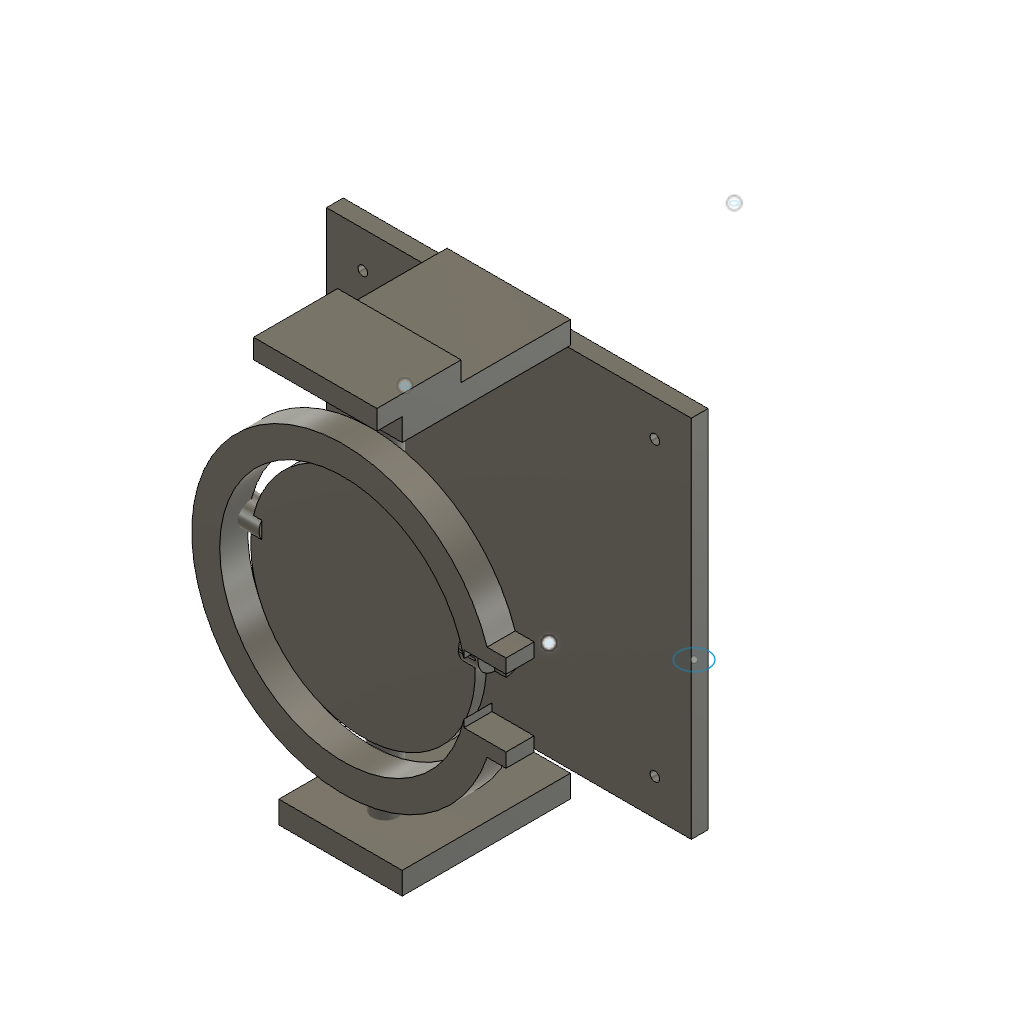
Gimbal2Axis (Autodesk Fusion 360 design; units mm, degrees)
part number: 2026-11-09-16-54-55-100
part number: 2026-11-09-16-54-55-282
part number: 2026-11-09-16-54-55-441
part number: 2026-11-09-16-54-55-850
Autodesk Fusion 360 part; units mm, degrees
ref_plane "工作平面1" through (0, 0, 0) normal (0, 0, 1) x (1, 0, 0) in component "Disc"
sketch "草图1" plane through (0, 0, 0) normal (0, 0, 1) x (1, 0, 0) in component "Disc"
  circle A0 centre (0, 0) radius 40
extrude "拉伸1" add sketch "草图1" along normal blind 4 makes body 1 in component "Disc"
ref_plane "工作平面2" through (36, 0, 0) normal (1, 0, 0) x (0, 1, 0) in component "Disc"
sketch "草图2" plane through (36, 0, 0) normal (1, 0, 0) x (0, 0, -1) in component "Disc"
  circle A0 centre (0, 6) radius 6
extrude "拉伸2" add sketch "草图2" along normal blind 11 bodies 1 in component "Disc"
ref_plane "工作平面3" through (-47, 0, 0) normal (1, 0, 0) x (0, 1, 0) in component "Disc"
sketch "草图3" plane through (-47, 0, 0) normal (1, 0, 0) x (0, 0, -1) in component "Disc"
  circle A0 centre (0, 6) radius 5
extrude "拉伸3" add sketch "草图3" along normal blind 11 bodies 1 in component "Disc"
ref_plane "工作平面4" through (34, 0, 0) normal (1, 0, 0) x (0, 1, 0) in component "Disc"
sketch "草图4" plane through (34, 0, 0) normal (1, 0, 0) x (0, 0, -1) in component "Disc"
  circle A0 centre (7, 6) radius 1.1
extrude "拉伸4" cut sketch "草图4" along normal blind 8 bodies 1 in component "Disc"
ref_plane "工作平面5" through (34, 0, 0) normal (1, 0, 0) x (0, 1, 0) in component "Disc"
sketch "草图5" plane through (34, 0, 0) normal (1, 0, 0) x (0, 0, -1) in component "Disc"
  circle A0 centre (-7, 6) radius 1.1
extrude "拉伸5" cut sketch "草图5" along normal blind 8 bodies 1 in component "Disc"
ref_plane "工作平面6" through (-48, 0, 0) normal (1, 0, 0) x (0, 1, 0) in component "Disc"
sketch "草图6" plane through (-48, 0, 0) normal (1, 0, 0) x (0, 0, -1) in component "Disc"
  circle A0 centre (0, 6) radius 1.55
extrude "拉伸6" cut sketch "草图6" along normal blind 13 bodies 1 in component "Disc"
ref_plane "工作平面7" through (0, 0, -0.1) normal (0, 0, 1) x (1, 0, 0) in component "Disc"
sketch "草图7" plane through (0, 0, -0.1) normal (0, 0, 1) x (1, 0, 0) in component "Disc"
  line L0 (-11, -8.5) -> (11, -8.5)
  line L1 (11, -8.5) -> (11, 8.5)
  line L2 (11, 8.5) -> (-11, 8.5)
  line L3 (-11, 8.5) -> (-11, -8.5)
extrude "拉伸7" cut sketch "草图7" along normal blind 1.6 bodies 1 in component "Disc"
ref_plane "工作平面1" through (0, 0, 0) normal (0, 0, 1) x (1, 0, 0) in component "Ring"
sketch "草图1 (2)" plane through (0, 0, 0) normal (0, 0, 1) x (1, 0, 0) in component "Ring"
  circle A0 centre (0, 0) radius 54
  circle A1 centre (0, 0) radius 44
extrude "拉伸1'" add sketch "草图1 (2)" along normal blind 10 separate body makes body 2 in component "Ring"
ref_plane "工作平面2" through (0, 0, 0) normal (0, 0, 1) x (1, 0, 0) in component "Ring"
sketch "草图2 (2)" plane through (0, 0, 0) normal (0, 0, 1) x (1, 0, 0) in component "Ring"
  line L0 (43, -12) -> (55, -12)
  line L1 (55, -12) -> (55, 12)
  line L2 (55, 12) -> (43, 12)
  line L3 (43, 12) -> (43, -12)
extrude "拉伸8" cut sketch "草图2 (2)" along normal blind 10 bodies 1 in component "Disc"
extrude "拉伸2'" cut sketch "草图2 (2)" along normal blind 10 bodies 2 in component "Ring"
ref_plane "工作平面3" through (0, 0, 0) normal (0, 0, 1) x (1, 0, 0) in component "Ring"
sketch "草图3 (2)" plane through (0, 0, 0) normal (0, 0, 1) x (1, 0, 0) in component "Ring"
  line L0 (50, 12) -> (58, 12)
  line L1 (58, 12) -> (58, 17)
  line L2 (58, 17) -> (50, 17)
  line L3 (50, 17) -> (50, 12)
extrude "拉伸3'" add sketch "草图3 (2)" along normal blind 10 bodies 2 in component "Ring"
ref_plane "工作平面4" through (0, 0, 0) normal (0, 0, 1) x (1, 0, 0) in component "Ring"
sketch "草图4 (2)" plane through (0, 0, 0) normal (0, 0, 1) x (1, 0, 0) in component "Ring"
  line L0 (50, -17) -> (58, -17)
  line L1 (58, -17) -> (58, -12)
  line L2 (58, -12) -> (50, -12)
  line L3 (50, -12) -> (50, -17)
extrude "拉伸4'" add sketch "草图4 (2)" along normal blind 10 bodies 2 in component "Ring"
ref_plane "工作平面5" through (49, 0, 0) normal (1, 0, 0) x (0, 1, 0) in component "Ring"
sketch "草图5 (2)" plane through (49, 0, 0) normal (1, 0, 0) x (0, 0, -1) in component "Ring"
  circle A0 centre (14.3, 5) radius 0.8
ref_plane "工作平面6" through (0, 42, 0) normal (0, 1, 0) x (0, 0, 1) in component "Ring"
sketch "草图6 (2)" plane through (0, 42, 0) normal (0, 1, 0) x (1, 0, 0) in component "Ring"
  circle A0 centre (0, 5) radius 5
extrude "拉伸5'" add sketch "草图6 (2)" along normal blind 32 bodies 2 in component "Ring"
ref_plane "工作平面7" through (0, -74, 0) normal (0, 1, 0) x (0, 0, 1) in component "Ring"
sketch "草图7 (2)" plane through (0, -74, 0) normal (0, 1, 0) x (1, 0, 0) in component "Ring"
  circle A0 centre (0, 5) radius 5
extrude "拉伸6'" add sketch "草图7 (2)" along normal blind 32 bodies 2 in component "Ring"
ref_plane "工作平面8" through (0, 68, 0) normal (0, 1, 0) x (0, 0, 1) in component "Ring"
sketch "草图8" plane through (0, 68, 0) normal (0, 1, 0) x (1, 0, 0) in component "Ring"
  circle A0 centre (7, 5) radius 1.1
ref_plane "工作平面9" through (0, -75, 0) normal (0, 1, 0) x (0, 0, 1) in component "Ring"
sketch "草图9" plane through (0, -75, 0) normal (0, 1, 0) x (1, 0, 0) in component "Ring"
  circle A0 centre (0, 5) radius 1.55
extrude "拉伸7'" cut sketch "草图9" along normal blind 33 bodies 2 in component "Ring"
ref_plane "工作平面10" through (-55, 0, 0) normal (1, 0, 0) x (0, 1, 0) in component "Ring"
sketch "草图10" plane through (-55, 0, 0) normal (1, 0, 0) x (0, 0, -1) in component "Ring"
  circle A0 centre (0, 5) radius 1.55
extrude "拉伸9" cut sketch "草图10" along normal blind 12 bodies 1 in component "Disc"
extrude "拉伸8'" cut sketch "草图10" along normal blind 12 bodies 2 in component "Ring"
ref_plane "工作平面1" through (0, 0, 0) normal (0, 0, 1) x (1, 0, 0) in component "Frame"
sketch "草图1 (3)" plane through (0, 0, 0) normal (0, 0, 1) x (1, 0, 0) in component "Frame"
  line L0 (-65, -65) -> (65, -65)
  line L1 (65, -65) -> (65, 65)
  line L2 (65, 65) -> (-65, 65)
  line L3 (-65, 65) -> (-65, -65)
extrude "拉伸1''" add sketch "草图1 (3)" along normal blind 6 separate body makes body 3 in component "Frame"
ref_plane "工作平面2" through (0, 0, 6) normal (0, 0, 1) x (1, 0, 0) in component "Frame"
sketch "草图2 (3)" plane through (0, 0, 6) normal (0, 0, 1) x (1, 0, 0) in component "Frame"
  line L0 (-22, 66) -> (22, 66)
  line L1 (22, 66) -> (22, 74)
  line L2 (22, 74) -> (-22, 74)
  line L3 (-22, 74) -> (-22, 66)
extrude "拉伸2''" add sketch "草图2 (3)" along normal blind 60 separate body makes body 4 in component "Frame"
ref_plane "工作平面3" through (0, 0, 6) normal (0, 0, 1) x (1, 0, 0) in component "Frame"
sketch "草图3 (3)" plane through (0, 0, 6) normal (0, 0, 1) x (1, 0, 0) in component "Frame"
  line L0 (-22, -74) -> (22, -74)
  line L1 (22, -74) -> (22, -66)
  line L2 (22, -66) -> (-22, -66)
  line L3 (-22, -66) -> (-22, -74)
extrude "拉伸3''" add sketch "草图3 (3)" along normal blind 60 separate body makes body 5 in component "Frame"
ref_plane "工作平面4" through (0, -75, 0) normal (0, 1, 0) x (0, 0, 1) in component "Frame"
sketch "草图4 (3)" plane through (0, -75, 0) normal (0, 1, 0) x (1, 0, 0) in component "Frame"
  circle A0 centre (0, 60) radius 5.25
ref_plane "工作平面5" through (0, 0, 45) normal (0, 0, 1) x (1, 0, 0) in component "Frame"
sketch "草图5 (3)" plane through (0, 0, 45) normal (0, 0, 1) x (1, 0, 0) in component "Frame"
  line L0 (-22, 74) -> (22, 74)
  line L1 (22, 74) -> (22, 81)
  line L2 (22, 81) -> (-22, 81)
  line L3 (-22, 81) -> (-22, 74)
extrude "拉伸4''" add sketch "草图5 (3)" along normal blind 30 bodies 4 in component "Frame"
ref_plane "工作平面6" through (0, 73, 0) normal (0, 1, 0) x (0, 0, 1) in component "Frame"
sketch "草图6 (3)" plane through (0, 73, 0) normal (0, 1, 0) x (1, 0, 0) in component "Frame"
  circle A0 centre (14.3, 60) radius 1.1
ref_plane "工作平面7" through (0, 0, -0.1) normal (0, 0, 1) x (1, 0, 0) in component "Frame"
sketch "草图7 (3)" plane through (0, 0, -0.1) normal (0, 0, 1) x (1, 0, 0) in component "Frame"
  circle A0 centre (-52, -52) radius 1.7
extrude "拉伸5''" cut sketch "草图7 (3)" along normal blind 7 bodies 3 in component "Frame"
ref_plane "工作平面8" through (0, 0, -0.1) normal (0, 0, 1) x (1, 0, 0) in component "Frame"
sketch "草图8 (2)" plane through (0, 0, -0.1) normal (0, 0, 1) x (1, 0, 0) in component "Frame"
  circle A0 centre (52, -52) radius 1.7
extrude "拉伸6''" cut sketch "草图8 (2)" along normal blind 7 bodies 3 in component "Frame"
ref_plane "工作平面9" through (0, 0, -0.1) normal (0, 0, 1) x (1, 0, 0) in component "Frame"
sketch "草图9 (2)" plane through (0, 0, -0.1) normal (0, 0, 1) x (1, 0, 0) in component "Frame"
  circle A0 centre (-52, 52) radius 1.7
extrude "拉伸7''" cut sketch "草图9 (2)" along normal blind 7 bodies 3 in component "Frame"
ref_plane "工作平面10" through (0, 0, -0.1) normal (0, 0, 1) x (1, 0, 0) in component "Frame"
sketch "草图10 (2)" plane through (0, 0, -0.1) normal (0, 0, 1) x (1, 0, 0) in component "Frame"
  circle A0 centre (52, 52) radius 1.7
extrude "拉伸8''" cut sketch "草图10 (2)" along normal blind 7 bodies 3 in component "Frame"
component "Disc" placed x (1, 0, 0) y (0, 1, 0) z (0, 0, 1) at (0, 0, 0)
component "Ring" placed x (1, 0, 0) y (0, 1, 0) z (0, 0, 1) at (0, 0, 0)
component "Frame" placed x (1, 0, 0) y (0, 1, 0) z (0, 0, 1) at (0, 0, 0)
